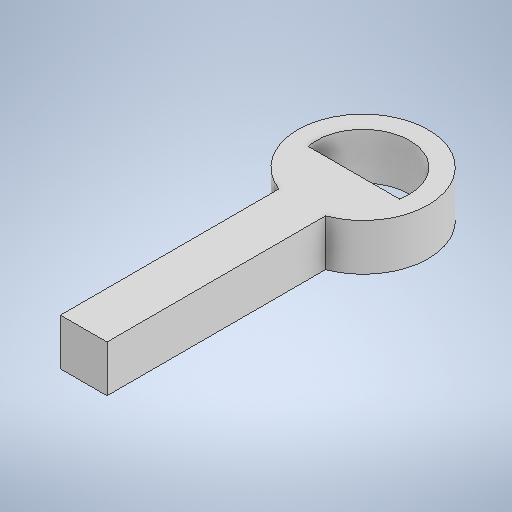
# Autodesk Inventor part: nakładka na popychacz
Saved by Autodesk Inventor 2025.2 (Build 292293000, 293)
## iProperties
Created: 2025-04-10
Part Number: nakładka na popychacz
Material: Generic
Document SubType Name: Modeling
Designer: makst
Density: 1 g/cm^3
Appearance: Default
Author: makst
Autodesk Inventor part; units mm, degrees
ref_plane "YZ Plane" through (0, 0, 0) normal (1, 0, 0) x (0, 1, 0)
ref_plane "XZ Plane" through (0, 0, 0) normal (0, 1, 0) x (-1, 0, 0)
ref_plane "XY Plane" through (0, 0, 0) normal (0, 0, 1) x (1, 0, 0)
sketch "Sketch1" plane through (0, 0, 0) normal (0, 1, 0) x (-1, 0, 0)
  line L0 (0, 0) -> (2.5, 0)
  line L1 (2.5, 0) -> (2.5, -15)
  line L2 (0, 0) -> (0, -15)
  line L3 (1.25, 0) -> (1.25, -23.4871) construction
  circle A0 centre (1.25, -15) radius 3.5
  circle A1 centre (1.25, -15) radius 2.5
  line L4 (3.75, -15) -> (-1.25, -15)
  line L5 (1.25, -15) -> (1.25, -15.5)
  line L6 (1.25, -15) -> (1.25, -14.5)
  line L7 (1.25, -14.5) -> (-1.1995, -14.5)
  line L8 (1.25, -14.5) -> (3.6995, -14.5)
  point P0 (0, -11.7308)
  point P1 (2.5, -11.7308)
  point P2 (3.6995, -15.5)
  point P3 (-1.1995, -15.5)
  dimension "d0" = 2.5
  dimension "d1" = 15
  dimension "d2" = 15
  dimension "d4" = 7
  dimension "d5" = 15
  dimension "d6" = 5
  dimension "d10" = 0.5
  constraints: 18 end point, 6 point on circle, 3 horizontal, 3 point on line, 3 vertical, 2 centre point, 1 coincident, 1 midpoint, 1 perpendicular
  measures "d0" distance of L0.start L0.end
  measures "d1" distance of L0.end L1.end
  measures "d2" distance of L0.start L2.end
  measures "d4" diameter of A0
  measures "d5" distance from line of A0.centre L0
  measures "d6" diameter of A1
  measures "d10" distance of L5.start L6.end
extrude "Extrusion1" add sketch "Sketch1" along normal blind 2.5 contours L0 L1 A0 L2 | A0 L1 A1 L2 | L2 A1 L1 A0 | A1 L1 L8 L7 L2 | L2 L7 A1 | A1 L8 L1
body "Solid1"
